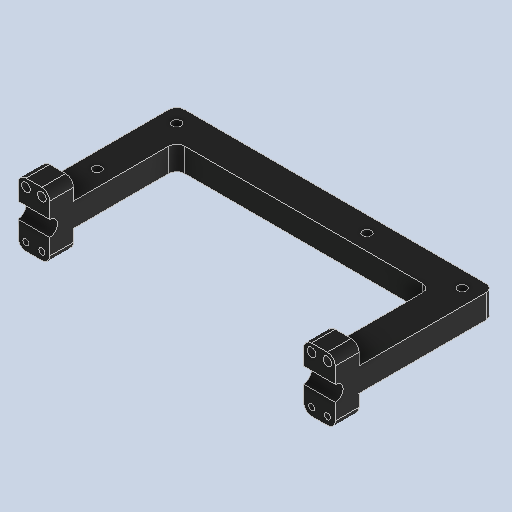
# Autodesk Inventor part: Stabilisatuer3.1
Saved by Autodesk Inventor 2025.3 (Build 293356000, 356)
## iProperties
Created: 2025-04-25
Part Number: Stabilisatuer3.1
Material: Gummi
Document SubType Name: Modeling
Designer: karle
Density: 0.93 g/cm^3
Appearance: Gummi - Schwarz
Author: karle
Autodesk Inventor part; units mm, degrees
ref_plane "YZ Plane" through (0, 0, 0) normal (1, 0, 0) x (0, 1, 0)
ref_plane "XZ Plane" through (0, 0, 0) normal (0, 1, 0) x (-1, 0, 0)
ref_plane "XY Plane" through (0, 0, 0) normal (0, 0, 1) x (1, 0, 0)
sketch "Skizze1" plane through (0, 0, 0) normal (0, 0, 1) x (1, 0, 0)
  line L0 (-100, 0) -> (-80, 0)
  line L1 (-80, 0) -> (-80, 80)
  line L2 (-80, 80) -> (80, 80)
  line L3 (80, 80) -> (80, 0)
  line L4 (80, 0) -> (100, 0)
  line L5 (100, 0) -> (100, 100)
  line L6 (100, 100) -> (-100, 100)
  line L7 (-100, 100) -> (-100, 0)
  line L8 (0, 90.2324) -> (0, 0)
  point P0 (90, 0)
  dimension "d0" = 160
  dimension "d1" = 80
  dimension "d2" = 0
  dimension "d3" = 80
  dimension "d4" = 200
  dimension "d5" = 20
  constraints: 18 end point, 6 perpendicular, 2 point on line, 1 horizontal, 1 midpoint, 1 vertical, 1 other
  measures "d0" distance between parallel lines of L1 L3
  measures "d1" distance from line of point (90, 0) L2
  measures "d2" vertical distance of L8.end point (90, 0)
  measures "d3" distance from line of L3 L8.end
  measures "d4" distance between parallel lines of L5 L7
  measures "d5" distance between parallel lines of L6 L2
extrude "Extrusion1" add sketch "Skizze1" along normal mid plane 15
sketch "Skizze2" plane through (-100, 0, 7.5) normal (0, -1, 0) x (1, 0, 0)
  line L0 (0, 12.5) -> (20, 12.5)
  line L1 (20, 12.5) -> (20, -27.5)
  line L2 (20, -27.5) -> (0, -27.5)
  line L3 (0, -27.5) -> (0, 12.5)
  line L4 (180, 12.5) -> (200, 12.5)
  line L5 (200, 12.5) -> (200, -27.5)
  line L6 (200, -27.5) -> (180, -27.5)
  line L7 (180, -27.5) -> (180, 12.5)
  line L8 (200, -15) -> (200, 0) projected
  line L9 (180, -15) -> (180, 0) projected
  line L10 (0, -15) -> (0, 0) projected
  line L11 (20, -15) -> (20, 0) projected
  line L12 (171.2366, -7.5) -> (-10.2497, -7.5)
  point P0 (100, -7.5)
  point P1 (190, -27.5)
  point P2 (190, 12.5)
  point P3 (185, -22.5)
  point P4 (15, -20.9733)
  point P5 (15, 5.9733)
  point P6 (185, 7.5)
  dimension "d8" = 40
  dimension "d9" = 12.5
  dimension "d12" = 30
  dimension "d14" = 5
  dimension "d16" = 5
  constraints: 18 end point, 4 collinear, 4 parallel, 3 horizontal, 2 midpoint, 2 perpendicular, 2 point on line, 2 symmetric about line, 1 other
  measures "d8" distance of point (190, -27.5) point (190, 12.5)
  measures "d9" distance from line of L8.end L0
  measures "d12" distance of point (185, 7.5) point (185, -22.5)
  measures "d14" distance from line of L7 point (185, -22.5)
  measures "d16" distance from line of L1 point (15, -20.973)
extrude "Extrusion2" add sketch "Skizze2" against normal blind 15
sketch "Skizze8" plane through (-100, 0, 20) normal (0, -1, 0) x (1, 0, 0)
  line L0 (0, -40) -> (0, 0) projected
  line L1 (20, 0) -> (0, 0) projected
  point P0 (100, -20)
  point P1 (5, -5)
  point P2 (5, -35)
  point P3 (185, -35)
  point P4 (185, -5)
  point P5 (15, -5)
  point P6 (15, -35)
  point P7 (195, -35)
  point P8 (195, -5)
  dimension "d55" = 5
  dimension "d56" = 30
  dimension "d57" = 180
  dimension "d58" = 5
  dimension "d87" = 10
  dimension "d88" = 10
  constraints: 6 horizontal alignment, 4 vertical alignment
  measures "d55" distance from line of L0 point (5, -5)
  measures "d56" distance of point (5, -5) point (5, -35)
  measures "d57" distance of point (185, -35) point (5, -35)
  measures "d58" distance from line of L1 point (5, -5)
  measures "d87" distance of point (5, -35) point (15, -35)
  measures "d88" distance of point (195, -5) point (185, -5)
hole "Bohrung5" at (-95, 0, 15) at (85, 0, 15) at (-85, 0, 15) at (95, 0, 15) direction (0, 1, 0) diameter 5.5 depth 13
hole "Bohrung6" at (-95, 0, -15) at (85, 0, -15) at (-85, 0, -15) at (95, 0, -15) direction (0, 1, 0) diameter 3.8 end through all
fillet "Rundung2" radius 5 8 edges at (-80, 7.5, 20) (-80, 7.5, -20) (-100, 7.5, 20) (-100, 7.5, -20) (100, 7.5, 20) (100, 7.5, -20) (80, 7.5, -20) (80, 7.5, 20)
fillet "Rundung3" radius 5 4 edges at (-80, 80, 0) (-100, 100, 0) (100, 100, 0) (80, 80, 0)
sketch "Skizze9" plane through (100, 0, 15) normal (1, 0, 0) x (0, 0, -1)
  point P0 (15, 0)
  point P1 (15, 0)
  dimension "d8" = 40
  dimension "d9" = 12.5
  dimension "d12" = 30
  dimension "d14" = 5
  dimension "d16" = 5
  constraints: 1 coincident
hole "Bohrung7" at (100, 0, 0) direction (-1, 0, 0) diameter 9.8 end through all
sketch "Skizze11" plane through (0, 0, 7.5) normal (0, 0, 1) x (1, 0, 0)
  point P0 (0, 0)
  point P1 (-90, 90)
  point P2 (90, 90)
  dimension "d89" = 180
  dimension "d90" = 90
  dimension "d91" = 90
  constraints: 1 horizontal alignment
  measures "d89" distance of point (90, 90) point (-90, 90)
  measures "d90" horizontal distance of point (90, 90) point (0, 0)
  measures "d91" horizontal distance of point (0, 0) point (90, 90)
hole "Bohrung8" at (90, 90, 7.5) at (-90, 90, 7.5) direction (0, 0, -1) diameter 5.7 end through all
sketch "Skizze12" plane through (0, 0, 7.5) normal (0, 0, 1) x (1, 0, 0)
  line L0 (95, 100) -> (-95, 100) projected
  line L1 (-80, 15) -> (-80, 75) projected
  line L2 (-85, 0) -> (-95, 0) projected
  line L3 (100, 15) -> (100, 95) projected
  point P0 (0, 0)
  point P1 (-90, 40)
  point P2 (30, 90)
  point P3 (-90, 0)
  dimension "d99" = 10
  dimension "d101" = 40
  dimension "d102" = 70
  dimension "d110" = 190
  constraints: 1 midpoint
  measures "d99" distance from line of L0 point (30, 90)
  measures "d101" distance of point (-90, 0) point (-90, 40)
  measures "d102" distance from line of L3 point (30, 90)
  measures "d110" distance from line of point (-90, 40) L3
hole "Bohrung9" at (-90, 40, 7.5) at (30, 90, 7.5) direction (0, 0, -1) diameter 5.5 end through all
